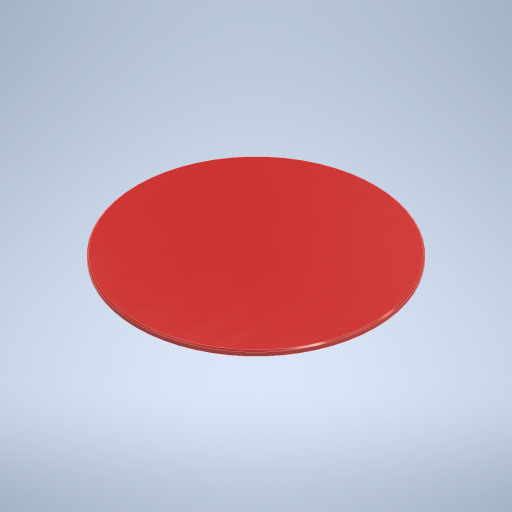
# Autodesk Inventor part: Podstava
Saved by Autodesk Inventor 2024 (Build 280153000, 153)
## iProperties
Created: 2025-11-04
Part Number: Podstava
Material: Všeobecné
Document SubType Name: Modeling
Designer: zak
Density: 1 g/cm^3
Appearance: Oranžovo-červená
Author: zak
Autodesk Inventor part; units mm, degrees
ref_plane "YZ Plane" through (0, 0, 0) normal (1, 0, 0) x (0, 1, 0)
ref_plane "XZ Plane" through (0, 0, 0) normal (0, 1, 0) x (-1, 0, 0)
ref_plane "XY Plane" through (0, 0, 0) normal (0, 0, 1) x (1, 0, 0)
sketch "Náčrt1" plane through (0, 0, 0) normal (0, 1, 0) x (-1, 0, 0)
  circle A0 centre (0, 0) radius 50
  dimension "d0" = 100
  constraints: 1 centre point, 1 coincident
  measures "d0" diameter of A0
extrude "Vysunutí1" add sketch "Náčrt1" along normal blind 2
chamfer "Zkosení1" distance 0.5 angle 45 1 edges at (50, 2, 0)
sketch "Náčrt2" plane through (0, 0, 0) normal (0, -1, 0) x (1, 0, 0)
  line L0 (-70, 0) -> (70, 0) projected
  line L1 (0, -70) -> (0, 70) projected
  arc A0 (-6.5505, 15.3485) -> (-22.8344, 3.7853) centre (-15, 10) ccw
  arc A1 (22.8344, 3.7853) -> (6.5505, 15.3485) centre (15, 10) ccw
  line L2 (0.4225, 5.6674) -> (6.5505, 15.3485)
  line L3 (-0.4225, 5.6674) -> (-6.5505, 15.3485)
  line L4 (-0.7834, -24.0124) -> (-22.8344, 3.7853)
  line L5 (0.7834, -24.0124) -> (22.8344, 3.7853)
  arc A2 (-0.7834, -24.0124) -> (0.7834, -24.0124) centre (0, -23.3909) ccw
  arc A3 (-0.4225, 5.6674) -> (0.4225, 5.6674) centre (0, 5.9348) ccw
  circle A4 centre (0, 0) radius 50 projected
  spline S0 degree 2 poles (-21.6689, 38.2319) (-21.9568, 38.0688) (-22.4291, 37.9603) (-22.6561, 37.9452) knots 0 0 0 1 2 2 2
  line L6 (-22.6561, 37.9452) -> (-22.9069, 38.3879)
  line L7 (-22.9069, 38.3879) -> (-22.8811, 38.4025)
  spline S1 degree 2 poles (-22.8811, 38.4025) (-22.6145, 38.3378) (-22.0717, 38.4068) (-21.8675, 38.5225) knots 0 0 0 1 2 2 2
  spline S2 degree 2 poles (-21.8675, 38.5225) (-21.5753, 38.6881) (-21.4141, 39.1002) (-21.5273, 39.3) knots 0 0 0 1 2 2 2
  spline S3 degree 2 poles (-21.5273, 39.3) (-21.6174, 39.4591) (-21.8863, 39.5679) (-22.0841, 39.5212) knots 0 0 0 1 2 2 2
  spline S4 degree 2 poles (-22.0841, 39.5212) (-22.2261, 39.4861) (-22.457, 39.4178) (-22.6315, 39.37) knots 0 0 0 1 2 2 2
  spline S5 degree 2 poles (-22.6315, 39.37) (-22.7898, 39.3286) (-23.0689, 39.3153) (-23.2027, 39.3559) knots 0 0 0 1 2 2 2
  spline S6 degree 2 poles (-23.2027, 39.3559) (-23.3342, 39.3977) (-23.5584, 39.583) (-23.6461, 39.7377) knots 0 0 0 1 2 2 2
  spline S7 degree 2 poles (-23.6461, 39.7377) (-23.8287, 40.0601) (-23.573, 40.7813) (-23.184, 41.0016) knots 0 0 0 1 2 2 2
  spline S8 degree 2 poles (-23.184, 41.0016) (-22.9605, 41.1283) (-22.5151, 41.2642) (-22.2979, 41.2765) knots 0 0 0 1 2 2 2
  line L8 (-22.2979, 41.2765) -> (-22.0592, 40.8553)
  line L9 (-22.0592, 40.8553) -> (-22.085, 40.8407)
  spline S9 degree 2 poles (-22.085, 40.8407) (-22.2776, 40.8849) (-22.7704, 40.8328) (-22.9875, 40.7099) knots 0 0 0 1 2 2 2
  spline S10 degree 2 poles (-22.9875, 40.7099) (-23.2325, 40.5711) (-23.4052, 40.1694) (-23.2993, 39.9825) knots 0 0 0 1 2 2 2
  spline S11 degree 2 poles (-23.2993, 39.9825) (-23.2043, 39.8148) (-22.9127, 39.716) (-22.7195, 39.7659) knots 0 0 0 1 2 2 2
  spline S12 degree 2 poles (-22.7195, 39.7659) (-22.5907, 39.7991) (-22.2224, 39.9056) (-22.0967, 39.9342) knots 0 0 0 1 2 2 2
  spline S13 degree 2 poles (-22.0967, 39.9342) (-21.7762, 40.005) (-21.3315, 39.8113) (-21.1915, 39.5641) knots 0 0 0 1 2 2 2
  spline S14 degree 2 poles (-21.1915, 39.5641) (-21.1026, 39.4072) (-21.059, 39.0345) (-21.1132, 38.8647) knots 0 0 0 1 2 2 2
  spline S15 degree 2 poles (-21.1132, 38.8647) (-21.1743, 38.6768) (-21.426, 38.3695) (-21.6689, 38.2319) knots 0 0 0 1 2 2 2
  line L10 (-23.1182, 42.2937) -> (-23.1421, 41.3887)
  line L11 (-23.1421, 41.3887) -> (-23.5461, 41.1598)
  line L12 (-23.5461, 41.1598) -> (-24.3346, 41.6046)
  line L13 (-24.3346, 41.6046) -> (-24.0509, 41.7653)
  line L14 (-24.0509, 41.7653) -> (-23.464, 41.4959)
  line L15 (-23.464, 41.4959) -> (-23.3933, 42.1378)
  line L16 (-23.3933, 42.1378) -> (-23.1182, 42.2937)
  line L17 (-19.7598, 39.314) -> (-20.9555, 41.7208)
  line L18 (-20.9555, 41.7208) -> (-21.8713, 41.2658)
  line L19 (-21.8713, 41.2658) -> (-22.0317, 41.5888)
  line L20 (-22.0317, 41.5888) -> (-19.8373, 42.6789)
  line L21 (-19.8373, 42.6789) -> (-19.6769, 42.3559)
  line L22 (-19.6769, 42.3559) -> (-20.5927, 41.901)
  line L23 (-20.5927, 41.901) -> (-19.397, 39.4942)
  line L24 (-19.397, 39.4942) -> (-19.7598, 39.314)
  line L25 (-20.8184, 43.4712) -> (-20.8914, 42.5689)
  line L26 (-20.8914, 42.5689) -> (-21.3073, 42.3623)
  line L27 (-21.3073, 42.3623) -> (-22.0705, 42.8492)
  line L28 (-22.0705, 42.8492) -> (-21.7785, 42.9943)
  line L29 (-21.7785, 42.9943) -> (-21.207, 42.6935)
  line L30 (-21.207, 42.6935) -> (-21.1016, 43.3306)
  line L31 (-21.1016, 43.3306) -> (-20.8184, 43.4712)
  line L32 (-18.4978, 39.9439) -> (-18.7519, 43.1504)
  line L33 (-18.7519, 43.1504) -> (-18.2932, 43.3466)
  line L34 (-18.2932, 43.3466) -> (-16.1496, 40.9484)
  line L35 (-16.1496, 40.9484) -> (-16.5425, 40.7803)
  line L36 (-16.5425, 40.7803) -> (-17.132, 41.455)
  line L37 (-17.132, 41.455) -> (-18.2016, 40.9974)
  line L38 (-18.2016, 40.9974) -> (-18.1208, 40.1051)
  line L39 (-18.1208, 40.1051) -> (-18.4978, 39.9439)
  line L40 (-17.3702, 41.7292) -> (-18.3684, 42.8631)
  line L41 (-18.3684, 42.8631) -> (-18.2355, 41.3591)
  line L42 (-18.2355, 41.3591) -> (-17.3702, 41.7292)
  spline S16 degree 2 poles (-15.0231, 41.298) (-15.3341, 41.185) (-15.8178, 41.1563) (-16.0442, 41.1791) knots 0 0 0 1 2 2 2
  line L43 (-16.0442, 41.1791) -> (-16.2181, 41.6573)
  line L44 (-16.2181, 41.6573) -> (-16.1902, 41.6674)
  spline S17 degree 2 poles (-16.1902, 41.6674) (-15.9381, 41.5594) (-15.3913, 41.5374) (-15.1708, 41.6175) knots 0 0 0 1 2 2 2
  spline S18 degree 2 poles (-15.1708, 41.6175) (-14.8551, 41.7323) (-14.6278, 42.1119) (-14.7062, 42.3278) knots 0 0 0 1 2 2 2
  spline S19 degree 2 poles (-14.7062, 42.3278) (-14.7687, 42.4996) (-15.0158, 42.6516) (-15.2186, 42.6383) knots 0 0 0 1 2 2 2
  spline S20 degree 2 poles (-15.2186, 42.6383) (-15.3644, 42.6273) (-15.6035, 42.5982) (-15.7835, 42.5801) knots 0 0 0 1 2 2 2
  spline S21 degree 2 poles (-15.7835, 42.5801) (-15.9464, 42.5655) (-16.2239, 42.5987) (-16.3491, 42.661) knots 0 0 0 1 2 2 2
  spline S22 degree 2 poles (-16.3491, 42.661) (-16.4719, 42.7241) (-16.6622, 42.944) (-16.723, 43.1111) knots 0 0 0 1 2 2 2
  spline S23 degree 2 poles (-16.723, 43.1111) (-16.8496, 43.4593) (-16.4777, 44.128) (-16.0575, 44.2808) knots 0 0 0 1 2 2 2
  spline S24 degree 2 poles (-16.0575, 44.2808) (-15.8161, 44.3686) (-15.3544, 44.4287) (-15.1381, 44.4048) knots 0 0 0 1 2 2 2
  line L45 (-15.1381, 44.4048) -> (-14.9726, 43.9498)
  line L46 (-14.9726, 43.9498) -> (-15.0005, 43.9397)
  spline S25 degree 2 poles (-15.0005, 43.9397) (-15.183, 44.0152) (-15.6777, 44.0457) (-15.9121, 43.9604) knots 0 0 0 1 2 2 2
  spline S26 degree 2 poles (-15.9121, 43.9604) (-16.1768, 43.8642) (-16.4138, 43.4968) (-16.3404, 43.2949) knots 0 0 0 1 2 2 2
  spline S27 degree 2 poles (-16.3404, 43.2949) (-16.2745, 43.1138) (-16.0034, 42.968) (-15.8046, 42.9851) knots 0 0 0 1 2 2 2
  spline S28 degree 2 poles (-15.8046, 42.9851) (-15.6721, 42.9964) (-15.2912, 43.0403) (-15.1624, 43.0477) knots 0 0 0 1 2 2 2
  spline S29 degree 2 poles (-15.1624, 43.0477) (-14.8347, 43.0643) (-14.4283, 42.7995) (-14.3312, 42.5325) knots 0 0 0 1 2 2 2
  spline S30 degree 2 poles (-14.3312, 42.5325) (-14.2696, 42.363) (-14.2884, 41.9883) (-14.3701, 41.8298) knots 0 0 0 1 2 2 2
  spline S31 degree 2 poles (-14.3701, 41.8298) (-14.4615, 41.6546) (-14.7608, 41.3934) (-15.0231, 41.298) knots 0 0 0 1 2 2 2
  line L47 (-12.9609, 42.0483) -> (-13.7406, 44.6201)
  line L48 (-13.7406, 44.6201) -> (-14.7192, 44.3234)
  line L49 (-14.7192, 44.3234) -> (-14.8238, 44.6685)
  line L50 (-14.8238, 44.6685) -> (-12.4789, 45.3794)
  line L51 (-12.4789, 45.3794) -> (-12.3743, 45.0342)
  line L52 (-12.3743, 45.0342) -> (-13.3529, 44.7376)
  line L53 (-13.3529, 44.7376) -> (-12.5733, 42.1658)
  line L54 (-12.5733, 42.1658) -> (-12.9609, 42.0483)
  line L55 (-9.1721, 43.0472) -> (-9.6142, 42.9415)
  line L56 (-9.6142, 42.9415) -> (-11.537, 45.1839)
  line L57 (-11.537, 45.1839) -> (-10.9258, 42.6279)
  line L58 (-10.9258, 42.6279) -> (-11.2934, 42.54)
  line L59 (-11.2934, 42.54) -> (-12.0022, 45.5044)
  line L60 (-12.0022, 45.5044) -> (-11.4425, 45.6382)
  line L61 (-11.4425, 45.6382) -> (-9.6873, 43.5767)
  line L62 (-9.6873, 43.5767) -> (-10.2485, 45.9237)
  line L63 (-10.2485, 45.9237) -> (-9.881, 46.0116)
  line L64 (-9.881, 46.0116) -> (-9.1721, 43.0472)
  line L65 (-8.5666, 43.1667) -> (-9.1009, 46.1675)
  line L66 (-9.1009, 46.1675) -> (-7.2235, 46.5018)
  line L67 (-7.2235, 46.5018) -> (-7.1603, 46.1467)
  line L68 (-7.1603, 46.1467) -> (-8.6388, 45.8835)
  line L69 (-8.6388, 45.8835) -> (-8.4925, 45.0616)
  line L70 (-8.4925, 45.0616) -> (-7.1137, 45.3071)
  line L71 (-7.1137, 45.3071) -> (-7.0505, 44.952)
  line L72 (-7.0505, 44.952) -> (-8.4293, 44.7065)
  line L73 (-8.4293, 44.7065) -> (-8.231, 43.5928)
  line L74 (-8.231, 43.5928) -> (-6.7525, 43.856)
  line L75 (-6.7525, 43.856) -> (-6.6892, 43.501)
  line L76 (-6.6892, 43.501) -> (-8.5666, 43.1667)
  line L77 (-7.7479, 47.5725) -> (-8.1632, 46.7208)
  line L78 (-8.1632, 46.7208) -> (-8.4648, 46.6671)
  line L79 (-8.4648, 46.6671) -> (-8.2391, 47.4851)
  line L80 (-8.2391, 47.4851) -> (-7.7479, 47.5725)
  line L81 (-5.2779, 43.7015) -> (-4.5308, 46.8301)
  line L82 (-4.5308, 46.8301) -> (-4.0339, 46.8753)
  line L83 (-4.0339, 46.8753) -> (-2.7344, 43.9329)
  line L84 (-2.7344, 43.9329) -> (-3.16, 43.8942)
  line L85 (-3.16, 43.8942) -> (-3.5127, 44.7178)
  line L86 (-3.5127, 44.7178) -> (-4.6713, 44.6124)
  line L87 (-4.6713, 44.6124) -> (-4.8696, 43.7387)
  line L88 (-4.8696, 43.7387) -> (-5.2779, 43.7015)
  line L89 (-3.6547, 45.0521) -> (-4.2546, 46.4386)
  line L90 (-4.2546, 46.4386) -> (-4.5919, 44.9669)
  line L91 (-4.5919, 44.9669) -> (-3.6547, 45.0521)
  line L92 (1.1032, 47.0517) -> (0.063, 44.0004)
  line L93 (0.063, 44.0004) -> (-0.3742, 43.999)
  line L94 (-0.3742, 43.999) -> (-1.4335, 47.0437)
  line L95 (-1.4335, 47.0437) -> (-0.9988, 47.0451)
  line L96 (-0.9988, 47.0451) -> (-0.1461, 44.516)
  line L97 (-0.1461, 44.516) -> (0.6907, 47.0504)
  line L98 (0.6907, 47.0504) -> (1.1032, 47.0517)
  line L99 (1.4383, 43.985) -> (1.5979, 47.0288)
  line L100 (1.5979, 47.0288) -> (3.5021, 46.929)
  line L101 (3.5021, 46.929) -> (3.4832, 46.5689)
  line L102 (3.4832, 46.5689) -> (1.9835, 46.6475)
  line L103 (1.9835, 46.6475) -> (1.9398, 45.8138)
  line L104 (1.9398, 45.8138) -> (3.3384, 45.7405)
  line L105 (3.3384, 45.7405) -> (3.3195, 45.3803)
  line L106 (3.3195, 45.3803) -> (1.9209, 45.4537)
  line L107 (1.9209, 45.4537) -> (1.8617, 44.3239)
  line L108 (1.8617, 44.3239) -> (3.3614, 44.2453)
  line L109 (3.3614, 44.2453) -> (3.3425, 43.8852)
  line L110 (3.3425, 43.8852) -> (1.4383, 43.985)
  spline S32 degree 2 poles (4.6244, 43.7017) (4.2953, 43.7366) (3.8481, 43.9231) (3.6546, 44.0429) knots 0 0 0 1 2 2 2
  line L111 (3.6546, 44.0429) -> (3.7083, 44.5489)
  line L112 (3.7083, 44.5489) -> (3.7378, 44.5458)
  spline S33 degree 2 poles (3.7378, 44.5458) (3.9169, 44.338) (4.3986, 44.0783) (4.6319, 44.0536) knots 0 0 0 1 2 2 2
  spline S34 degree 2 poles (4.6319, 44.0536) (4.966, 44.0182) (5.3368, 44.2595) (5.361, 44.488) knots 0 0 0 1 2 2 2
  spline S35 degree 2 poles (5.361, 44.488) (5.3803, 44.6697) (5.225, 44.9147) (5.0369, 44.9918) knots 0 0 0 1 2 2 2
  spline S36 degree 2 poles (5.0369, 44.9918) (4.9011, 45.0459) (4.6734, 45.1247) (4.5037, 45.1874) knots 0 0 0 1 2 2 2
  spline S37 degree 2 poles (4.5037, 45.1874) (4.351, 45.2458) (4.1162, 45.3974) (4.0311, 45.5082) knots 0 0 0 1 2 2 2
  spline S38 degree 2 poles (4.0311, 45.5082) (3.9484, 45.6188) (3.8739, 45.9) (3.8926, 46.0768) knots 0 0 0 1 2 2 2
  spline S39 degree 2 poles (3.8926, 46.0768) (3.9317, 46.4453) (4.5593, 46.8829) (5.0039, 46.8358) knots 0 0 0 1 2 2 2
  spline S40 degree 2 poles (5.0039, 46.8358) (5.2593, 46.8087) (5.7006, 46.6601) (5.8845, 46.5437) knots 0 0 0 1 2 2 2
  line L113 (5.8845, 46.5437) -> (5.8335, 46.0623)
  line L114 (5.8335, 46.0623) -> (5.804, 46.0654)
  spline S41 degree 2 poles (5.804, 46.0654) (5.6731, 46.2134) (5.242, 46.4579) (4.9939, 46.4842) knots 0 0 0 1 2 2 2
  spline S42 degree 2 poles (4.9939, 46.4842) (4.7139, 46.5138) (4.3397, 46.2877) (4.3171, 46.074) knots 0 0 0 1 2 2 2
  spline S43 degree 2 poles (4.3171, 46.074) (4.2968, 45.8825) (4.4764, 45.6324) (4.6625, 45.5605) knots 0 0 0 1 2 2 2
  spline S44 degree 2 poles (4.6625, 45.5605) (4.7866, 45.5126) (5.1481, 45.3848) (5.267, 45.335) knots 0 0 0 1 2 2 2
  spline S45 degree 2 poles (5.267, 45.335) (5.5688, 45.2061) (5.8178, 44.7898) (5.7878, 44.5073) knots 0 0 0 1 2 2 2
  spline S46 degree 2 poles (5.7878, 44.5073) (5.7688, 44.328) (5.5874, 43.9995) (5.4445, 43.8929) knots 0 0 0 1 2 2 2
  spline S47 degree 2 poles (5.4445, 43.8929) (5.2855, 43.7756) (4.902, 43.6722) (4.6244, 43.7017) knots 0 0 0 1 2 2 2
  line L115 (6.1042, 43.5831) -> (6.5864, 46.5928)
  line L116 (6.5864, 46.5928) -> (8.4692, 46.2911)
  line L117 (8.4692, 46.2911) -> (8.4122, 45.935)
  line L118 (8.4122, 45.935) -> (6.9293, 46.1726)
  line L119 (6.9293, 46.1726) -> (6.7973, 45.3482)
  line L120 (6.7973, 45.3482) -> (8.1801, 45.1267)
  line L121 (8.1801, 45.1267) -> (8.1231, 44.7706)
  line L122 (8.1231, 44.7706) -> (6.7402, 44.9922)
  line L123 (6.7402, 44.9922) -> (6.5613, 43.8751)
  line L124 (6.5613, 43.8751) -> (8.0441, 43.6376)
  line L125 (8.0441, 43.6376) -> (7.9871, 43.2815)
  line L126 (7.9871, 43.2815) -> (6.1042, 43.5831)
  line L127 (10.1501, 42.8257) -> (8.4226, 43.1926)
  line L128 (8.4226, 43.1926) -> (9.0558, 46.1741)
  line L129 (9.0558, 46.1741) -> (9.452, 46.0899)
  line L130 (9.452, 46.0899) -> (8.8938, 43.4612)
  line L131 (8.8938, 43.4612) -> (10.2251, 43.1785)
  line L132 (10.2251, 43.1785) -> (10.1501, 42.8257)
  line L133 (10.459, 42.7476) -> (11.2415, 45.6935)
  line L134 (11.2415, 45.6935) -> (13.0845, 45.2039)
  line L135 (13.0845, 45.2039) -> (12.9919, 44.8554)
  line L136 (12.9919, 44.8554) -> (11.5405, 45.2409)
  line L137 (11.5405, 45.2409) -> (11.3261, 44.4341)
  line L138 (11.3261, 44.4341) -> (12.6797, 44.0745)
  line L139 (12.6797, 44.0745) -> (12.5871, 43.7259)
  line L140 (12.5871, 43.7259) -> (11.2335, 44.0855)
  line L141 (11.2335, 44.0855) -> (10.9431, 42.9922)
  line L142 (10.9431, 42.9922) -> (12.3945, 42.6066)
  line L143 (12.3945, 42.6066) -> (12.3019, 42.2581)
  line L144 (12.3019, 42.2581) -> (10.459, 42.7476)
  line L145 (13.0612, 46.3959) -> (12.3251, 45.7992)
  line L146 (12.3251, 45.7992) -> (12.0291, 45.8778)
  line L147 (12.0291, 45.8778) -> (12.579, 46.524)
  line L148 (12.579, 46.524) -> (13.0612, 46.3959)
  line L149 (17.0861, 43.8537) -> (15.0676, 41.3402)
  line L150 (15.0676, 41.3402) -> (14.6561, 41.488)
  line L151 (14.6561, 41.488) -> (14.6989, 44.7114)
  line L152 (14.6989, 44.7114) -> (15.108, 44.5644)
  line L153 (15.108, 44.5644) -> (15.0469, 41.8961)
  line L154 (15.0469, 41.8961) -> (16.6979, 43.9931)
  line L155 (16.6979, 43.9931) -> (17.0861, 43.8537)
  spline S48 degree 2 poles (19.4073, 42.4875) (19.4858, 42.233) (19.4278, 41.6124) (19.277, 41.2631) knots 0 0 0 1 2 2 2
  spline S49 degree 2 poles (19.277, 41.2631) (19.1302, 40.923) (18.72, 40.4463) (18.4765, 40.3308) knots 0 0 0 1 2 2 2
  spline S50 degree 2 poles (18.4765, 40.3308) (18.2199, 40.2101) (17.6838, 40.2209) (17.4094, 40.3394) knots 0 0 0 1 2 2 2
  spline S51 degree 2 poles (17.4094, 40.3394) (17.126, 40.4617) (16.7556, 40.8502) (16.6713, 41.1099) knots 0 0 0 1 2 2 2
  spline S52 degree 2 poles (16.6713, 41.1099) (16.5905, 41.3654) (16.6541, 41.9863) (16.8029, 42.331) knots 0 0 0 1 2 2 2
  spline S53 degree 2 poles (16.8029, 42.331) (16.9546, 42.6825) (17.3602, 43.1423) (17.6044, 43.2656) knots 0 0 0 1 2 2 2
  spline S54 degree 2 poles (17.6044, 43.2656) (17.8479, 43.3811) (18.387, 43.3771) (18.6682, 43.2558) knots 0 0 0 1 2 2 2
  spline S55 degree 2 poles (18.6682, 43.2558) (18.9539, 43.1324) (19.3259, 42.7351) (19.4073, 42.4875) knots 0 0 0 1 2 2 2
  spline S56 degree 2 poles (18.8892, 41.4305) (19.0087, 41.7072) (19.0735, 42.1877) (19.0253, 42.3753) knots 0 0 0 1 2 2 2
  spline S57 degree 2 poles (19.0253, 42.3753) (18.9768, 42.5684) (18.7265, 42.8486) (18.5315, 42.9327) knots 0 0 0 1 2 2 2
  spline S58 degree 2 poles (18.5315, 42.9327) (18.3296, 43.0199) (17.9651, 43.0104) (17.7848, 42.9107) knots 0 0 0 1 2 2 2
  spline S59 degree 2 poles (17.7848, 42.9107) (17.612, 42.8158) (17.3081, 42.4358) (17.1907, 42.1636) knots 0 0 0 1 2 2 2
  spline S60 degree 2 poles (17.1907, 42.1636) (16.9528, 41.6126) (17.1629, 40.8278) (17.5507, 40.6604) knots 0 0 0 1 2 2 2
  spline S61 degree 2 poles (17.5507, 40.6604) (17.9385, 40.493) (18.6514, 40.8794) (18.8892, 41.4305) knots 0 0 0 1 2 2 2
  line L156 (20.6471, 38.8685) -> (19.0684, 39.6602)
  line L157 (19.0684, 39.6602) -> (20.4348, 42.3848)
  line L158 (20.4348, 42.3848) -> (20.7969, 42.2032)
  line L159 (20.7969, 42.2032) -> (19.5922, 39.801)
  line L160 (19.5922, 39.801) -> (20.8088, 39.1909)
  line L161 (20.8088, 39.1909) -> (20.6471, 38.8685)
  line L162 (20.9262, 38.7149) -> (22.4281, 41.3672)
  line L163 (22.4281, 41.3672) -> (24.0874, 40.4277)
  line L164 (24.0874, 40.4277) -> (23.9097, 40.1138)
  line L165 (23.9097, 40.1138) -> (22.6029, 40.8538)
  line L166 (22.6029, 40.8538) -> (22.1915, 40.1273)
  line L167 (22.1915, 40.1273) -> (23.4102, 39.4373)
  line L168 (23.4102, 39.4373) -> (23.2325, 39.1235)
  line L169 (23.2325, 39.1235) -> (22.0138, 39.8135)
  line L170 (22.0138, 39.8135) -> (21.4564, 38.8291)
  line L171 (21.4564, 38.8291) -> (22.7632, 38.0892)
  line L172 (22.7632, 38.0892) -> (22.5855, 37.7754)
  line L173 (22.5855, 37.7754) -> (20.9262, 38.7149)
  point P0 (0, 5)
  point P1 (0, -25)
  dimension "d7" = 20
  dimension "d8" = 20
  dimension "d11" = 30
  dimension "d12" = 5
  dimension "d13" = 25
  dimension "d14" = 1
  dimension "d15" = 0.5
  constraints: 9 tangent, 8 end point, 8 point on circle, 6 point on line, 4 centre point, 1 symmetric about line, 1 other
  measures "d7" diameter of A0
  measures "d8" diameter of A1
  measures "d11" distance of A1.centre A0.centre
  measures "d12" distance from line of L0 point (0, 5)
  measures "d13" distance from line of L0 point (0, -25)
  measures "d14" radius of A2
  measures "d15" radius of A3
emboss "Reliéf1" sketch "Náčrt2" operation cut depth 0.5 direction (0, 1, 0) contours L4 A0 L3 A3 L1 L0 | L0 L1 A2 L4 | L1 A3 L2 A1 L5 L0 | L0 L5 A2 L1 | L97 L98 L92 L93 L1 | L1 L93 L94 L95 L96 L97 | S0 L6 L7 S1 S2 S3 S4 S5 S6 S7 S8 L8 L9 S9 S10 S11 S12 S13 S14 S15 | L10 L11 L12 L13 L14 L15 L16 | L17 L18 L19 L20 L21 L22 L23 L24 | L25 L26 L27 L28 L29 L30 L31 | L32 L33 L34 L35 L36 L37 L38 L39 | S16 L43 L44 S17 S18 S19 S20 S21 S22 S23 S24 L45 L46 S25 S26 S27 S28 S29 S30 S31 | L47 L48 L49 L50 L51 L52 L53 L54 | L55 L56 L57 L58 L59 L60 L61 L62 L63 L64 | L65 L66 L67 L68 L69 L70 L71 L72 L73 L74 L75 L76 | L77 L78 L79 L80 | L81 L82 L83 L84 L85 L86 L87 L88 | L99 L100 L101 L102 L103 L104 L105 L106 L107 L108 L109 L110 | S32 L111 L112 S33 S34 S35 S36 S37 S38 S39 S40 L113 L114 S41 S42 S43 S44 S45 S46 S47 | L115 L116 L117 L118 L119 L120 L121 L122 L123 L124 L125 L126 | L127 L128 L129 L130 L131 L132 | L133 L134 L135 L136 L137 L138 L139 L140 L141 L142 L143 L144 | L145 L146 L147 L148 | L149 L150 L151 L152 L153 L154 L155 | S48 S49 S50 S51 S52 S53 S54 S55 | L156 L157 L158 L159 L160 L161 | L162 L163 L164 L165 L166 L167 L168 L169 L170 L171 L172 L173
